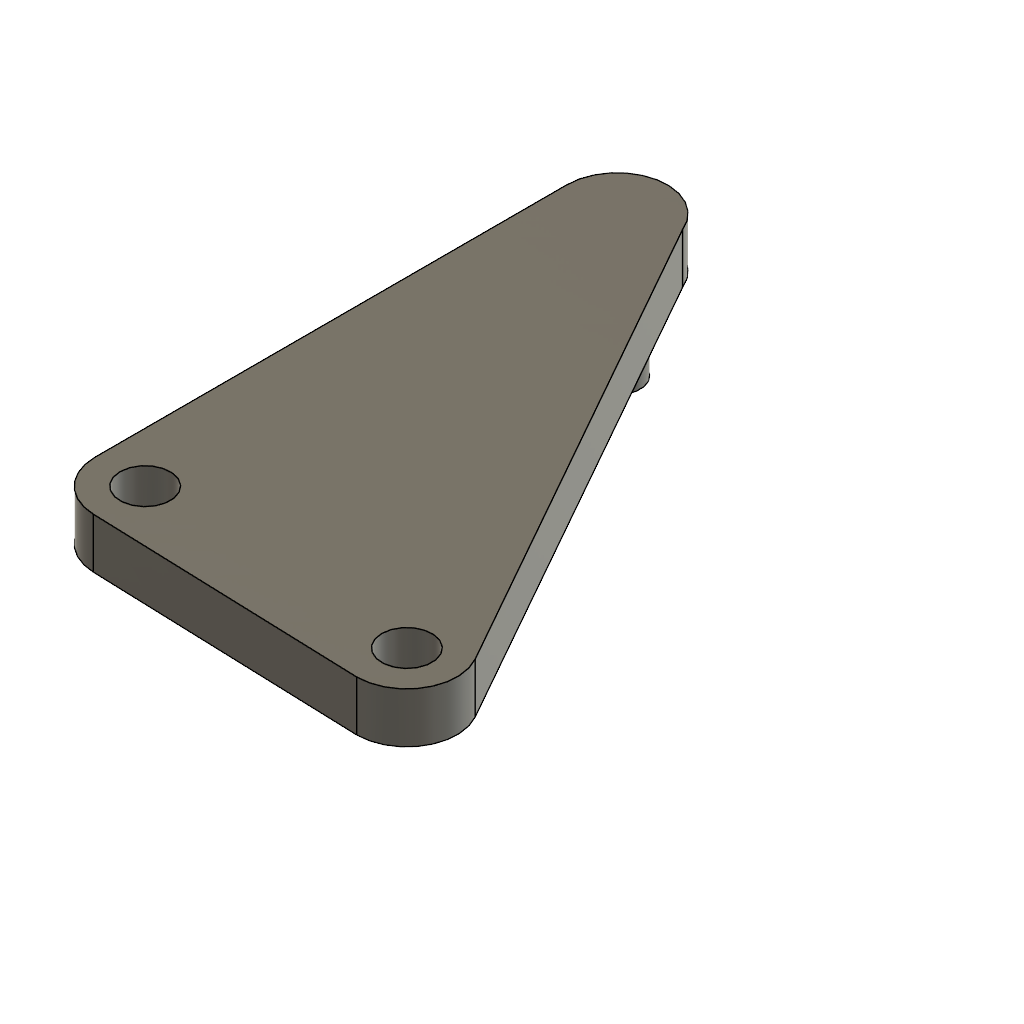
link 6 (Autodesk Fusion 360 design; units mm, degrees)
part number: 2026-11-18-20-17-13-715
Autodesk Fusion 360 part; units mm, degrees
note: some values were not read from the file. Set by a fixed rule: which sketch regions a step uses.
sketch "Sketch2" plane through (0, 0, 0) normal (0, 1, 0) x (1, 0, 0)
  line L0 (2.4985, -47.0857) -> (26.9841, -47.9255)
  circle A0 centre (0, -47) radius 2.5
  circle A1 centre (0, -47) radius 5
  circle A2 centre (26.9841, -47.9255) radius 2.5
  circle A3 centre (26.9841, -47.9255) radius 5
  circle A4 centre (0, 0) radius 2.5
  line L1 (-5, 0) -> (-5, -47)
  line L2 (26.9841, -47.9255) -> (26.9841, -52.9255)
  line L3 (26.9841, -52.9255) -> (-0.1709, -51.9971)
  line L4 (0, 0) -> (0, -2.5)
  line L5 (0, -42) -> (0, -47)
  arc A5 (2.4531, -4.3569) -> (-5, 0) centre (0, 0) ccw
  line L6 (26.9841, -47.9255) -> (2.4531, -4.3569)
  line L7 (1.2266, -2.1784) -> (0, 0)
  line L8 (4, 3) -> (31.3391, -45.4691)
  dimension "d12" = 47
  dimension "d13" = 27
  dimension "d14" = 55
  dimension "d15" = 5
  dimension "d16" = 10
  dimension "d17" = 5
  dimension "d18" = 10
  dimension "d19" = 5
  dimension "d20" = 10
  constraint coincident A4.centre L4.start
  constraint vertical L4
  constraint coincident A0.centre A1.centre
  constraint concentric A0 A1
  constraint coincident L0.end A2.centre
  constraint concentric A2 A3
  constraint coincident A1 L1.end
  constraint tangent A1 L1
  constraint coincident A3 L2.end
  constraint vertical L2
  constraint coincident A1 L3.end
  constraint tangent A1 L3
  constraint coincident A4 L4.end
  constraint collinear L4 L5
  constraint coincident A1 L5.start
  constraint coincident A4 L7.start
  constraint collinear L6 L7
  constraint coincident A0 L0.start
  constraint coincident A5 L8.start
  constraint coincident A3 L8.end
  constraint tangent A3 L8
  measures "d12" distance of A4.centre A0.centre
  measures "d13" distance of A0.centre L0.end
  measures "d14" distance of A4.centre L0.end
  measures "d15" diameter of A0
  measures "d16" diameter of A1
  measures "d17" diameter of A2
  measures "d18" diameter of A3
  measures "d19" diameter of A4
  measures "d20" diameter of A5
extrude "Extrude2" add sketch "Sketch2" along normal blind 5 contours L0 A0 A1 L5 | L0 A0 A1 L5 | L0 A1 A3 L1 A5 L6 L8 | L0 A2 A3 L2 | A2 A3 L2 L6 | L0 A1 A3 L3 | L0 A2 A3 L6 | A3 A5 L6 L8 | A5 L8
sketch "Sketch3" plane through (0, 5, 0) normal (0, 1, 0) x (-1, 0, 0)
  circle A0 centre (0, 0) radius 2.5
  circle A1 centre (0, 47) radius 2.5
  circle A2 centre (-26.9841, 47.9255) radius 2.5
  arc A3 (-4.6366, -1.8715) -> (5, 0) centre (0, 0) ccw
  line L0 (5, 0) -> (5, 47)
  arc A4 (5, 47) -> (0.1709, 51.9971) centre (0, 47) ccw
  line L1 (0.1709, 51.9971) -> (-26.9841, 52.9255)
  arc A5 (-26.9841, 52.9255) -> (-31.3391, 45.4691) centre (-26.9841, 47.9255) ccw
  line L2 (-31.3391, 45.4691) -> (-4.6366, -1.8715)
  circle A6 centre (0, 0) radius 2.5
  constraint coincident A0.centre A3.centre
extrude "Extrude3" add sketch "Sketch3" against normal blind 6 contours A0 A6
sketch "Sketch4" plane through (0, -1, 0) normal (0, -1, 0) x (1, 0, 0)
  circle A0 centre (0, 0) radius 2.5
  circle A1 centre (0, 0) radius 2.3
  dimension "d25" = 4.6
  constraint coincident A0.centre A1.centre
  measures "d25" diameter of A1
extrude "Extrude4" cut sketch "Sketch4" against normal blind 1
extrude "Extrude5" add 1 faces at (-0.5201, -1, -0.0372) along direction (0, -1, 0) blind 5
sketch "Sketch5" plane through (0, -6, 0) normal (0, -1, 0) x (1, 0, 0)
  circle A0 centre (0, 0) radius 2.3
  circle A1 centre (0, 0) radius 2
  dimension "d30" = 4
  constraint coincident A0.centre A1.centre
  measures "d30" diameter of A1
extrude "Extrude6" add sketch "Sketch5" along normal blind 1 contours A1
sketch "Sketch6" plane through (0, -7, 0) normal (0, -1, 0) x (1, 0, 0)
  circle A0 centre (0, 0) radius 2
  circle A1 centre (0, 0) radius 2.3
  dimension "d33" = 4.6
  constraint coincident A0.centre A1.centre
  measures "d33" diameter of A1
extrude "Extrude7" add sketch "Sketch6" along normal blind 2 contours A0 | A1
